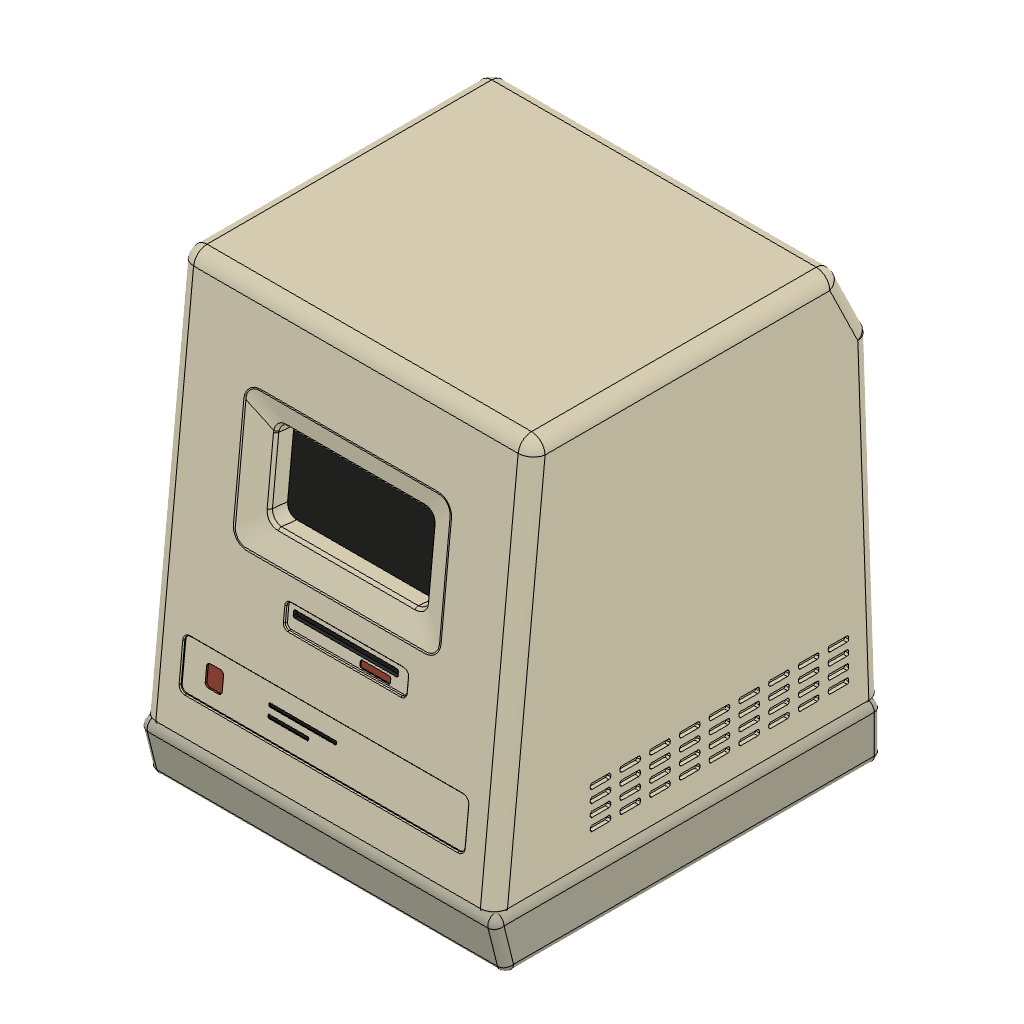
tokometer_stand_v3 (Autodesk Fusion 360 design; units mm, degrees)
part number: 2026-10-07-14-09-25-264
Autodesk Fusion 360 part; units mm, degrees
(part 1 of 2)
ref_plane "Plano de trabalho1" through (-26, 0, 0) normal (1, 0, 0) x (0, 1, 0)
sketch "Esboço1" plane through (-26, 0, 0) normal (1, 0, 0) x (0, 0, -1)
  line L0 (0, 8) -> (5.8, 65.7)
  line L1 (5.8, 65.7) -> (50.9693, 65.7)
  line L2 (50.9693, 65.7) -> (55.8466, 55.7)
  line L3 (55.8466, 55.7) -> (57.5, 8)
  line L4 (57.5, 8) -> (0, 8)
extrude "Extrusão1" add sketch "Esboço1" along normal blind 52 makes body 1
fillet "Continuous exterior corner blends" radius 2 11 edges at (-26, 36.85, -2.9) (26, 36.85, -2.9) (0, 65.7, -5.8) (-26, 65.7, -28.3846) (26, 65.7, -28.3846) (0, 65.7, -50.9693) (-26, 60.7, -53.408) (26, 60.7, -53.408) (0, 55.7, -55.8466) (-26, 31.85, -56.6733) (26, 31.85, -56.6733) on bodies 1
fillet "Lower shell edge break" radius 0.35 8 edges at (-25.4142, 8, -56.9139) (-25.4142, 8, -0.5887) (25.4142, 8, -0.5887) (25.4142, 8, -56.9139) (-26, 8, -28.7544) (0, 8, -57.5) (26, 8, -28.7544) (0, 8, 0) on bodies 1
ref_plane "Plano de trabalho2" through (-24, 0, 0) normal (1, 0, 0) x (0, 1, 0)
sketch "Esboço2" plane through (-24, 0, 0) normal (1, 0, 0) x (0, 0, -1)
  line L0 (2.5126, 8) -> (8.1116, 63.7)
  line L1 (8.1116, 63.7) -> (49.7196, 63.7)
  line L2 (49.7196, 63.7) -> (53.8638, 55.2029)
  line L3 (53.8638, 55.2029) -> (55.5, 8)
  line L4 (55.5, 8) -> (2.5126, 8)
extrude "Extrusão2" cut sketch "Esboço2" along normal blind 48 bodies 1
ref_plane "Plano de trabalho3" through (0, 35.8925, -5.3163) normal (0, 0.100016, 0.994986) x (0, -0.994986, 0.100016)
sketch "Esboço3" plane through (0, -0.17, -1.6913) normal (0, 0.100016, 0.994986) x (0, -0.994986, 0.100016)
  line L0 (-26.6423, -17.4) -> (-59.7923, -17.4)
  line L1 (-59.9923, -17.2) -> (-59.9923, 17.2)
  line L2 (-59.7923, 17.4) -> (-26.6423, 17.4)
  line L3 (-26.4423, 17.2) -> (-26.4423, -17.2)
  arc A0 (-59.9923, -17.2) -> (-59.7923, -17.4) centre (-59.7923, -17.2) ccw
  arc A1 (-59.7923, 17.4) -> (-59.9923, 17.2) centre (-59.7923, 17.2) ccw
  arc A2 (-26.4423, 17.2) -> (-26.6423, 17.4) centre (-26.6423, 17.2) ccw
  arc A3 (-26.6423, -17.4) -> (-26.4423, -17.2) centre (-26.6423, -17.2) ccw
  constraint tangent L0 A0
  constraint tangent L1 A0
  constraint tangent L1 A1
  constraint tangent L2 A1
  constraint tangent L2 A2
  constraint tangent L3 A2
  constraint tangent L3 A3
  constraint tangent L0 A3
extrude "Extrusão3" add sketch "Esboço3" against normal blind 1.5 bodies 1
sketch "Esboço4" plane through (0, 0.08, 0.7961) normal (0, 0.100016, 0.994986) x (0, -0.994986, 0.100016)
  line L0 (-36.5623, -15.22) -> (-52.1223, -15.22)
  line L1 (-54.1223, -13.22) -> (-54.1223, 13.22)
  line L2 (-52.1223, 15.22) -> (-36.5623, 15.22)
  line L3 (-34.5623, 13.22) -> (-34.5623, -13.22)
  arc A0 (-54.1223, -13.22) -> (-52.1223, -15.22) centre (-52.1223, -13.22) ccw
  arc A1 (-52.1223, 15.22) -> (-54.1223, 13.22) centre (-52.1223, 13.22) ccw
  arc A2 (-34.5623, 13.22) -> (-36.5623, 15.22) centre (-36.5623, 13.22) ccw
  arc A3 (-36.5623, -15.22) -> (-34.5623, -13.22) centre (-36.5623, -13.22) ccw
  constraint tangent L0 A0
  constraint tangent L1 A0
  constraint tangent L1 A1
  constraint tangent L2 A1
  constraint tangent L2 A2
  constraint tangent L3 A2
  constraint tangent L3 A3
  constraint tangent L0 A3
ref_plane "Plano de trabalho4" through (0, 36.0025, -4.2219) normal (0, 0.100016, 0.994986) x (0, -0.994986, 0.100016)
sketch "Esboço5" plane through (0, -0.06, -0.5969) normal (0, 0.100016, 0.994986) x (0, -0.994986, 0.100016)
  line L0 (-39.6623, -11.62) -> (-49.0223, -11.62)
  line L1 (-50.5223, -10.12) -> (-50.5223, 10.12)
  line L2 (-49.0223, 11.62) -> (-39.6623, 11.62)
  line L3 (-38.1623, 10.12) -> (-38.1623, -10.12)
  arc A0 (-50.5223, -10.12) -> (-49.0223, -11.62) centre (-49.0223, -10.12) ccw
  arc A1 (-49.0223, 11.62) -> (-50.5223, 10.12) centre (-49.0223, 10.12) ccw
  arc A2 (-38.1623, 10.12) -> (-39.6623, 11.62) centre (-39.6623, 10.12) ccw
  arc A3 (-39.6623, -11.62) -> (-38.1623, -10.12) centre (-39.6623, -10.12) ccw
  constraint tangent L0 A0
  constraint tangent L1 A0
  constraint tangent L1 A1
  constraint tangent L2 A1
  constraint tangent L2 A2
  constraint tangent L3 A2
  constraint tangent L3 A3
  constraint tangent L0 A3
loft "Recessed screen surround" cut profiles "Esboço4", "Esboço5" section 1 section 2 bodies 1
sketch "Esboço6" plane through (0, -0.06, -0.5969) normal (0, 0.100016, 0.994986) x (0, -0.994986, 0.100016)
  line L0 (-39.6623, -11.62) -> (-49.0223, -11.62)
  line L1 (-50.5223, -10.12) -> (-50.5223, 10.12)
  line L2 (-49.0223, 11.62) -> (-39.6623, 11.62)
  line L3 (-38.1623, 10.12) -> (-38.1623, -10.12)
  arc A0 (-50.5223, -10.12) -> (-49.0223, -11.62) centre (-49.0223, -10.12) ccw
  arc A1 (-49.0223, 11.62) -> (-50.5223, 10.12) centre (-49.0223, 10.12) ccw
  arc A2 (-38.1623, 10.12) -> (-39.6623, 11.62) centre (-39.6623, 10.12) ccw
  arc A3 (-39.6623, -11.62) -> (-38.1623, -10.12) centre (-39.6623, -10.12) ccw
  constraint tangent L0 A0
  constraint tangent L1 A0
  constraint tangent L1 A1
  constraint tangent L2 A1
  constraint tangent L2 A2
  constraint tangent L3 A2
  constraint tangent L3 A3
  constraint tangent L0 A3
extrude "OLED aperture" cut sketch "Esboço6" against normal blind 3.6 bodies 1
fillet "Soft screen entry lip" radius 0.7 1 edges at (15.22, 36.459, -2.8607) on bodies 1
fillet "Rounded screen throat" radius 0.5 8 edges at (-11.2027, 49.7494, -5.6037) (0, 50.209, -5.6499) (11.2027, 49.7494, -5.6037) (11.62, 44.06, -5.0318) (11.2027, 38.3706, -4.4599) (0, 37.911, -4.4137) (-11.2027, 38.3705, -4.4599) (-11.62, 44.06, -5.0318) on bodies 1
ref_plane "Plano de trabalho5" through (0, 35.7425, -6.8088) normal (0, 0.100016, 0.994986) x (0, -0.994986, 0.100016)
ref_plane "Plano de trabalho6" through (0, 35.4524, -9.6943) normal (0, 0.100016, 0.994986) x (0, -0.994986, 0.100016)
ref_plane "Plano de trabalho7" through (0, 35.4824, -9.3958) normal (0, 0.100016, 0.994986) x (0, -0.994986, 0.100016)
sketch "Esboço7" plane through (0, -0.32, -3.1838) normal (0, 0.100016, 0.994986) x (0, -0.994986, 0.100016)
  line L0 (-28.6423, -15.4) -> (-57.7923, -15.4)
  line L1 (-57.9923, -15.2) -> (-57.9923, -14.1)
  line L2 (-57.7923, -13.9) -> (-28.6423, -13.9)
  line L3 (-28.4423, -14.1) -> (-28.4423, -15.2)
  arc A0 (-57.9923, -15.2) -> (-57.7923, -15.4) centre (-57.7923, -15.2) ccw
  arc A1 (-57.7923, -13.9) -> (-57.9923, -14.1) centre (-57.7923, -14.1) ccw
  arc A2 (-28.4423, -14.1) -> (-28.6423, -13.9) centre (-28.6423, -14.1) ccw
  arc A3 (-28.6423, -15.4) -> (-28.4423, -15.2) centre (-28.6423, -15.2) ccw
  constraint tangent L0 A0
  constraint tangent L1 A0
  constraint tangent L1 A1
  constraint tangent L2 A1
  constraint tangent L2 A2
  constraint tangent L3 A2
  constraint tangent L3 A3
  constraint tangent L0 A3
extrude "Extrusão5" add sketch "Esboço7" against normal blind 2.9 bodies 1
sketch "Esboço8" plane through (0, -0.6101, -6.0693) normal (0, 0.100016, 0.994986) x (0, -0.994986, 0.100016)
  line L0 (-28.6423, -15.4) -> (-57.7923, -15.4)
  line L1 (-57.9923, -15.2) -> (-57.9923, -12.65)
  line L2 (-57.7923, -12.45) -> (-28.6423, -12.45)
  line L3 (-28.4423, -12.65) -> (-28.4423, -15.2)
  arc A0 (-57.9923, -15.2) -> (-57.7923, -15.4) centre (-57.7923, -15.2) ccw
  arc A1 (-57.7923, -12.45) -> (-57.9923, -12.65) centre (-57.7923, -12.65) ccw
  arc A2 (-28.4423, -12.65) -> (-28.6423, -12.45) centre (-28.6423, -12.65) ccw
  arc A3 (-28.6423, -15.4) -> (-28.4423, -15.2) centre (-28.6423, -15.2) ccw
  constraint tangent L0 A0
  constraint tangent L1 A0
  constraint tangent L1 A1
  constraint tangent L2 A1
  constraint tangent L2 A2
  constraint tangent L3 A2
  constraint tangent L3 A3
  constraint tangent L0 A3
extrude "Extrusão6" add sketch "Esboço8" against normal blind 1.2 bodies 1
sketch "Esboço9" plane through (0, -0.32, -3.1838) normal (0, 0.100016, 0.994986) x (0, -0.994986, 0.100016)
  line L0 (-56.6923, -14.15) -> (-57.7923, -14.15)
  line L1 (-57.9923, -13.95) -> (-57.9923, -11.35)
  line L2 (-57.7923, -11.15) -> (-56.6923, -11.15)
  line L3 (-56.4923, -11.35) -> (-56.4923, -13.95)
  arc A0 (-57.9923, -13.95) -> (-57.7923, -14.15) centre (-57.7923, -13.95) ccw
  arc A1 (-57.7923, -11.15) -> (-57.9923, -11.35) centre (-57.7923, -11.35) ccw
  arc A2 (-56.4923, -11.35) -> (-56.6923, -11.15) centre (-56.6923, -11.35) ccw
  arc A3 (-56.6923, -14.15) -> (-56.4923, -13.95) centre (-56.6923, -13.95) ccw
  constraint tangent L0 A0
  constraint tangent L1 A0
  constraint tangent L1 A1
  constraint tangent L2 A1
  constraint tangent L2 A2
  constraint tangent L3 A2
  constraint tangent L3 A3
  constraint tangent L0 A3
extrude "Extrusão7" add sketch "Esboço9" against normal blind 2.9 bodies 1
sketch "Esboço10" plane through (0, -0.5801, -5.7708) normal (0, 0.100016, 0.994986) x (0, -0.994986, 0.100016)
  line L0 (-34.0923, -13.53) -> (-36.6923, -13.53)
  line L1 (-36.8923, -13.33) -> (-36.8923, -12.77)
  line L2 (-36.6923, -12.57) -> (-34.0923, -12.57)
  line L3 (-33.8923, -12.77) -> (-33.8923, -13.33)
  arc A0 (-36.8923, -13.33) -> (-36.6923, -13.53) centre (-36.6923, -13.33) ccw
  arc A1 (-36.6923, -12.57) -> (-36.8923, -12.77) centre (-36.6923, -12.77) ccw
  arc A2 (-33.8923, -12.77) -> (-34.0923, -12.57) centre (-34.0923, -12.77) ccw
  arc A3 (-34.0923, -13.53) -> (-33.8923, -13.33) centre (-34.0923, -13.33) ccw
  constraint tangent L0 A0
  constraint tangent L1 A0
  constraint tangent L1 A1
  constraint tangent L2 A1
  constraint tangent L2 A2
  constraint tangent L3 A2
  constraint tangent L3 A3
  constraint tangent L0 A3
extrude "Extrusão8" add sketch "Esboço10" against normal blind 0.3 bodies 1
sketch "Esboço11" plane through (0, -0.5801, -5.7708) normal (0, 0.100016, 0.994986) x (0, -0.994986, 0.100016)
  line L0 (-47.9923, -13.53) -> (-50.5923, -13.53)
  line L1 (-50.7923, -13.33) -> (-50.7923, -12.77)
  line L2 (-50.5923, -12.57) -> (-47.9923, -12.57)
  line L3 (-47.7923, -12.77) -> (-47.7923, -13.33)
  arc A0 (-50.7923, -13.33) -> (-50.5923, -13.53) centre (-50.5923, -13.33) ccw
  arc A1 (-50.5923, -12.57) -> (-50.7923, -12.77) centre (-50.5923, -12.77) ccw
  arc A2 (-47.7923, -12.77) -> (-47.9923, -12.57) centre (-47.9923, -12.77) ccw
  arc A3 (-47.9923, -13.53) -> (-47.7923, -13.33) centre (-47.9923, -13.33) ccw
  constraint tangent L0 A0
  constraint tangent L1 A0
  constraint tangent L1 A1
  constraint tangent L2 A1
  constraint tangent L2 A2
  constraint tangent L3 A2
  constraint tangent L3 A3
  constraint tangent L0 A3
extrude "Extrusão9" add sketch "Esboço11" against normal blind 0.3 bodies 1
sketch "Esboço12" plane through (0, -0.32, -3.1838) normal (0, 0.100016, 0.994986) x (0, -0.994986, 0.100016)
  line L0 (-28.6423, 13.9) -> (-57.7923, 13.9)
  line L1 (-57.9923, 14.1) -> (-57.9923, 15.2)
  line L2 (-57.7923, 15.4) -> (-28.6423, 15.4)
  line L3 (-28.4423, 15.2) -> (-28.4423, 14.1)
  arc A0 (-57.9923, 14.1) -> (-57.7923, 13.9) centre (-57.7923, 14.1) ccw
  arc A1 (-57.7923, 15.4) -> (-57.9923, 15.2) centre (-57.7923, 15.2) ccw
  arc A2 (-28.4423, 15.2) -> (-28.6423, 15.4) centre (-28.6423, 15.2) ccw
  arc A3 (-28.6423, 13.9) -> (-28.4423, 14.1) centre (-28.6423, 14.1) ccw
  constraint tangent L0 A0
  constraint tangent L1 A0
  constraint tangent L1 A1
  constraint tangent L2 A1
  constraint tangent L2 A2
  constraint tangent L3 A2
  constraint tangent L3 A3
  constraint tangent L0 A3
extrude "Extrusão10" add sketch "Esboço12" against normal blind 2.9 bodies 1
sketch "Esboço13" plane through (0, -0.6101, -6.0693) normal (0, 0.100016, 0.994986) x (0, -0.994986, 0.100016)
  line L0 (-28.6423, 12.45) -> (-57.7923, 12.45)
  line L1 (-57.9923, 12.65) -> (-57.9923, 15.2)
  line L2 (-57.7923, 15.4) -> (-28.6423, 15.4)
  line L3 (-28.4423, 15.2) -> (-28.4423, 12.65)
  arc A0 (-57.9923, 12.65) -> (-57.7923, 12.45) centre (-57.7923, 12.65) ccw
  arc A1 (-57.7923, 15.4) -> (-57.9923, 15.2) centre (-57.7923, 15.2) ccw
  arc A2 (-28.4423, 15.2) -> (-28.6423, 15.4) centre (-28.6423, 15.2) ccw
  arc A3 (-28.6423, 12.45) -> (-28.4423, 12.65) centre (-28.6423, 12.65) ccw
  constraint tangent L0 A0
  constraint tangent L1 A0
  constraint tangent L1 A1
  constraint tangent L2 A1
  constraint tangent L2 A2
  constraint tangent L3 A2
  constraint tangent L3 A3
  constraint tangent L0 A3
extrude "Extrusão11" add sketch "Esboço13" against normal blind 1.2 bodies 1
sketch "Esboço14" plane through (0, -0.32, -3.1838) normal (0, 0.100016, 0.994986) x (0, -0.994986, 0.100016)
  line L0 (-56.6923, 11.15) -> (-57.7923, 11.15)
  line L1 (-57.9923, 11.35) -> (-57.9923, 13.95)
  line L2 (-57.7923, 14.15) -> (-56.6923, 14.15)
  line L3 (-56.4923, 13.95) -> (-56.4923, 11.35)
  arc A0 (-57.9923, 11.35) -> (-57.7923, 11.15) centre (-57.7923, 11.35) ccw
  arc A1 (-57.7923, 14.15) -> (-57.9923, 13.95) centre (-57.7923, 13.95) ccw
  arc A2 (-56.4923, 13.95) -> (-56.6923, 14.15) centre (-56.6923, 13.95) ccw
  arc A3 (-56.6923, 11.15) -> (-56.4923, 11.35) centre (-56.6923, 11.35) ccw
  constraint tangent L0 A0
  constraint tangent L1 A0
  constraint tangent L1 A1
  constraint tangent L2 A1
  constraint tangent L2 A2
  constraint tangent L3 A2
  constraint tangent L3 A3
  constraint tangent L0 A3
extrude "Extrusão12" add sketch "Esboço14" against normal blind 2.9 bodies 1
sketch "Esboço15" plane through (0, -0.5801, -5.7708) normal (0, 0.100016, 0.994986) x (0, -0.994986, 0.100016)
  line L0 (-34.0923, 12.57) -> (-36.6923, 12.57)
  line L1 (-36.8923, 12.77) -> (-36.8923, 13.33)
  line L2 (-36.6923, 13.53) -> (-34.0923, 13.53)
  line L3 (-33.8923, 13.33) -> (-33.8923, 12.77)
  arc A0 (-36.8923, 12.77) -> (-36.6923, 12.57) centre (-36.6923, 12.77) ccw
  arc A1 (-36.6923, 13.53) -> (-36.8923, 13.33) centre (-36.6923, 13.33) ccw
  arc A2 (-33.8923, 13.33) -> (-34.0923, 13.53) centre (-34.0923, 13.33) ccw
  arc A3 (-34.0923, 12.57) -> (-33.8923, 12.77) centre (-34.0923, 12.77) ccw
  constraint tangent L0 A0
  constraint tangent L1 A0
  constraint tangent L1 A1
  constraint tangent L2 A1
  constraint tangent L2 A2
  constraint tangent L3 A2
  constraint tangent L3 A3
  constraint tangent L0 A3
extrude "Extrusão13" add sketch "Esboço15" against normal blind 0.3 bodies 1
sketch "Esboço16" plane through (0, -0.5801, -5.7708) normal (0, 0.100016, 0.994986) x (0, -0.994986, 0.100016)
  line L0 (-47.9923, 12.57) -> (-50.5923, 12.57)
  line L1 (-50.7923, 12.77) -> (-50.7923, 13.33)
  line L2 (-50.5923, 13.53) -> (-47.9923, 13.53)
  line L3 (-47.7923, 13.33) -> (-47.7923, 12.77)
  arc A0 (-50.7923, 12.77) -> (-50.5923, 12.57) centre (-50.5923, 12.77) ccw
  arc A1 (-50.5923, 13.53) -> (-50.7923, 13.33) centre (-50.5923, 13.33) ccw
  arc A2 (-47.7923, 13.33) -> (-47.9923, 13.53) centre (-47.9923, 13.33) ccw
  arc A3 (-47.9923, 12.57) -> (-47.7923, 12.77) centre (-47.9923, 12.77) ccw
  constraint tangent L0 A0
  constraint tangent L1 A0
  constraint tangent L1 A1
  constraint tangent L2 A1
  constraint tangent L2 A2
  constraint tangent L3 A2
  constraint tangent L3 A3
  constraint tangent L0 A3
extrude "Extrusão14" add sketch "Esboço16" against normal blind 0.3 bodies 1
ref_plane "Plano de trabalho8" through (0, 0, -58.5) normal (0, 0, 1) x (1, 0, 0)
sketch "Esboço17" plane through (0, 0, -58.5) normal (0, 0, 1) x (1, 0, 0)
  line L0 (-5, 10.2) -> (5, 10.2)
  line L1 (6.5, 11.7) -> (6.5, 15.7)
  line L2 (5, 17.2) -> (-5, 17.2)
  line L3 (-6.5, 15.7) -> (-6.5, 11.7)
  arc A0 (5, 10.2) -> (6.5, 11.7) centre (5, 11.7) ccw
  arc A1 (6.5, 15.7) -> (5, 17.2) centre (5, 15.7) ccw
  arc A2 (-5, 17.2) -> (-6.5, 15.7) centre (-5, 15.7) ccw
  arc A3 (-6.5, 11.7) -> (-5, 10.2) centre (-5, 11.7) ccw
  constraint tangent L0 A0
  constraint tangent L1 A0
  constraint tangent L1 A1
  constraint tangent L2 A1
  constraint tangent L2 A2
  constraint tangent L3 A2
  constraint tangent L3 A3
  constraint tangent L0 A3
extrude "Extrusão15" cut sketch "Esboço17" along normal blind 6 bodies 1
ref_plane "Plano de trabalho9" through (0, 8.65, 0) normal (0, 1, 0) x (0, 0, 1)
sketch "Esboço18" plane through (0, 8.65, 0) normal (0, 1, 0) x (1, 0, 0)
  line L0 (23.5, 18.0063) -> (24.5, 18.0063)
  line L1 (24.5, 18.0063) -> (24.5, 40.0063)
  line L2 (24.5, 40.0063) -> (23.5, 40.0063)
  line L3 (23.5, 40.0063) -> (23.5, 18.0063)
extrude "Extrusão16" cut sketch "Esboço18" along normal blind 1 bodies 1
ref_plane "Plano de trabalho10" through (0, 8.65, 0) normal (0, 1, 0) x (0, 0, 1)
sketch "Esboço19" plane through (0, 8.65, 0) normal (0, 1, 0) x (1, 0, 0)
  line L0 (-24.5, 18.0063) -> (-23.5, 18.0063)
  line L1 (-23.5, 18.0063) -> (-23.5, 40.0063)
  line L2 (-23.5, 40.0063) -> (-24.5, 40.0063)
  line L3 (-24.5, 40.0063) -> (-24.5, 18.0063)
extrude "Extrusão17" cut sketch "Esboço19" along normal blind 1 bodies 1
ref_plane "Plano de trabalho11" through (-26.4, 0, 0) normal (1, 0, 0) x (0, 1, 0)
sketch "Esboço20" plane through (-26.4, 0, 0) normal (1, 0, 0) x (0, 0, -1)
  line L0 (1.6, 0) -> (57.1, 0)
  line L1 (57.1, 0) -> (57.1, 8)
  line L2 (57.1, 8) -> (-0.4, 8)
  line L3 (-0.4, 8) -> (1.6, 0)
extrude "Extrusão18" add sketch "Esboço20" along normal blind 52.8 separate body makes body 2
fillet "Molded base perimeter" radius 1.2 12 edges at (-26.4, 8, -28.35) (0, 8, 0.4) (26.4, 8, -28.35) (0, 8, -57.1) (-26.4, 4, -57.1) (26.4, 4, -57.1) (0, 0, -57.1) (-26.4, 0, -29.35) (26.4, 0, -29.35) (0, 0, -1.6) (-26.4, 4, -0.6) (26.4, 4, -0.6) on bodies 2
ref_plane "Plano de trabalho12" through (0, 8, 0) normal (0, 1, 0) x (0, 0, 1)
sketch "Esboço21" plane through (0, 8, 0) normal (0, 1, 0) x (1, 0, 0)
  line L0 (-23.8, 2.9438) -> (23.8, 2.9438)
  line L1 (23.8, 2.9438) -> (23.8, 55.3)
  line L2 (23.8, 55.3) -> (-23.8, 55.3)
  line L3 (-23.8, 55.3) -> (-23.8, 2.9438)
  line L4 (-22.2, 4.5438) -> (22.2, 4.5438)
  line L5 (22.2, 4.5438) -> (22.2, 53.7)
  line L6 (22.2, 53.7) -> (-22.2, 53.7)
  line L7 (-22.2, 53.7) -> (-22.2, 4.5438)
extrude "Extrusão19" add sketch "Esboço21" along normal blind 2.3 bodies 2
ref_plane "Plano de trabalho13" through (0, 8, 0) normal (0, 1, 0) x (0, 0, 1)
sketch "Esboço22" plane through (0, 8, 0) normal (0, 1, 0) x (1, 0, 0)
  line L0 (-7.5, 53.2) -> (7.5, 53.2)
  line L1 (7.5, 53.2) -> (7.5, 55.8)
  line L2 (7.5, 55.8) -> (-7.5, 55.8)
  line L3 (-7.5, 55.8) -> (-7.5, 53.2)
extrude "Extrusão20" cut sketch "Esboço22" along normal blind 2.8 bodies 2
ref_plane "Plano de trabalho14" through (0, 8.75, 0) normal (0, 1, 0) x (0, 0, 1)
sketch "Esboço23" plane through (0, 8.75, 0) normal (0, 1, 0) x (1, 0, 0)
  line L0 (23.6, 19.0063) -> (24.2, 19.0063)
  line L1 (24.2, 19.0063) -> (24.2, 39.0063)
  line L2 (24.2, 39.0063) -> (23.6, 39.0063)
  line L3 (23.6, 39.0063) -> (23.6, 19.0063)
extrude "Extrusão21" add sketch "Esboço23" along normal blind 0.8 bodies 2
ref_plane "Plano de trabalho15" through (0, 8.75, 0) normal (0, 1, 0) x (0, 0, 1)
sketch "Esboço24" plane through (0, 8.75, 0) normal (0, 1, 0) x (1, 0, 0)
  line L0 (-24.2, 19.0063) -> (-23.6, 19.0063)
  line L1 (-23.6, 19.0063) -> (-23.6, 39.0063)
  line L2 (-23.6, 39.0063) -> (-24.2, 39.0063)
  line L3 (-24.2, 39.0063) -> (-24.2, 19.0063)
extrude "Extrusão22" add sketch "Esboço24" along normal blind 0.8 bodies 2
ref_plane "Plano de trabalho16" through (0, 1.5, 0) normal (0, 1, 0) x (0, 0, 1)
sketch "Esboço25" plane through (0, 1.5, 0) normal (0, 1, 0) x (1, 0, 0)
  line L0 (-13.35, 5.8811) -> (-12.05, 5.8811)
  line L1 (-12.05, 5.8811) -> (-12.05, 52.3811)
  line L2 (-12.05, 52.3811) -> (-13.35, 52.3811)
  line L3 (-13.35, 52.3811) -> (-13.35, 5.8811)
extrude "Extrusão23" cut sketch "Esboço25" along normal blind 7 bodies 2
ref_plane "Plano de trabalho17" through (0, 1.5, 0) normal (0, 1, 0) x (0, 0, 1)
sketch "Esboço26" plane through (0, 1.5, 0) normal (0, 1, 0) x (1, 0, 0)
  line L0 (12.05, 5.8811) -> (13.35, 5.8811)
  line L1 (13.35, 5.8811) -> (13.35, 52.3811)
  line L2 (13.35, 52.3811) -> (12.05, 52.3811)
  line L3 (12.05, 52.3811) -> (12.05, 5.8811)
extrude "Extrusão24" cut sketch "Esboço26" along normal blind 7 bodies 2
ref_plane "Plano de trabalho18" through (0, 0, -6.8) normal (0, 0, 1) x (1, 0, 0)
sketch "Esboço27" plane through (0, 0, -6.8) normal (0, 0, 1) x (1, 0, 0)
  line L0 (-13.65, 28.3) -> (13.65, 28.3)
  line L1 (13.65, 28.3) -> (13.65, 56.1)
  line L2 (13.65, 56.1) -> (-13.65, 56.1)
  line L3 (-13.65, 56.1) -> (-13.65, 28.3)
extrude "Extrusão25" add sketch "Esboço27" along normal blind 1.6 separate body makes body 3
ref_plane "Plano de trabalho19" through (0, 0, -5.2) normal (0, 0, 1) x (1, 0, 0)
sketch "Esboço28" plane through (0, 0, -5.2) normal (0, 0, 1) x (1, 0, 0)
  line L0 (-13.35, 32.55) -> (13.35, 32.55)
  line L1 (13.35, 32.55) -> (13.35, 51.85)
  line L2 (13.35, 51.85) -> (-13.35, 51.85)
  line L3 (-13.35, 51.85) -> (-13.35, 32.55)
extrude "Extrusão26" add sketch "Esboço28" along normal blind 1.2 bodies 3
move_body "Mover1" bodies 3 to x (1, 0, 0) y (0, 0.994986, -0.100016) z (0, 0.100016, 0.994986) at (0, 0.2216, 0.7819)
ref_plane "Plano de trabalho20" through (0, 10.5, 0) normal (0, 1, 0) x (0, 0, 1)
sketch "Esboço29" plane through (0, 10.5, 0) normal (0, 1, 0) x (1, 0, 0)
  line L0 (-14.25, 3.3811) -> (14.25, 3.3811)
  line L1 (14.25, 3.3811) -> (14.25, 54.8811)
  line L2 (14.25, 54.8811) -> (-14.25, 54.8811)
  line L3 (-14.25, 54.8811) -> (-14.25, 3.3811)
extrude "Extrusão27" add sketch "Esboço29" along normal blind 1.6 separate body makes body 4
ref_plane "Plano de trabalho21" through (0, 8, 0) normal (0, 1, 0) x (0, 0, 1)
sketch "Esboço30" plane through (0, 8, 0) normal (0, 1, 0) x (1, 0, 0)
  line L0 (-13.97, 10.1311) -> (-11.43, 10.1311)
  line L1 (-11.43, 10.1311) -> (-11.43, 48.1311)
  line L2 (-11.43, 48.1311) -> (-13.97, 48.1311)
  line L3 (-13.97, 48.1311) -> (-13.97, 10.1311)
extrude "Extrusão28" add sketch "Esboço30" along normal blind 2.5 bodies 4
ref_plane "Plano de trabalho22" through (0, 8, 0) normal (0, 1, 0) x (0, 0, 1)
sketch "Esboço31" plane through (0, 8, 0) normal (0, 1, 0) x (1, 0, 0)
  line L0 (11.43, 10.1311) -> (13.97, 10.1311)
  line L1 (13.97, 10.1311) -> (13.97, 48.1311)
  line L2 (13.97, 48.1311) -> (11.43, 48.1311)
  line L3 (11.43, 48.1311) -> (11.43, 10.1311)
extrude "Extrusão29" add sketch "Esboço31" along normal blind 2.5 bodies 4
ref_plane "Plano de trabalho23" through (0, 12.1, 0) normal (0, 1, 0) x (0, 0, 1)
sketch "Esboço32" plane through (0, 12.1, 0) normal (0, 1, 0) x (1, 0, 0)
  line L0 (-9, 3.8811) -> (9, 3.8811)
  line L1 (9, 3.8811) -> (9, 21.8811)
  line L2 (9, 21.8811) -> (-9, 21.8811)
  line L3 (-9, 21.8811) -> (-9, 3.8811)
extrude "Extrusão30" add sketch "Esboço32" along normal blind 3.1 bodies 4
ref_plane "Plano de trabalho24" through (0, 12.1, 0) normal (0, 1, 0) x (0, 0, 1)
sketch "Esboço33" plane through (0, 12.1, 0) normal (0, 1, 0) x (1, 0, 0)
  line L0 (-4.5, 47.5811) -> (4.5, 47.5811)
  line L1 (4.5, 47.5811) -> (4.5, 54.8811)
  line L2 (4.5, 54.8811) -> (-4.5, 54.8811)
  line L3 (-4.5, 54.8811) -> (-4.5, 47.5811)
extrude "Extrusão31" add sketch "Esboço33" along normal blind 3.2 bodies 4
sketch "Esboço34" plane through (0, 0.08, 0.7961) normal (0, 0.100016, 0.994986) x (0, -0.994986, 0.100016)
  line L0 (-28.5123, -7) -> (-30.6123, -7)
  line L1 (-31.2623, -6.35) -> (-31.2623, 10.35)
  line L2 (-30.6123, 11) -> (-28.5123, 11)
  line L3 (-27.8623, 10.35) -> (-27.8623, -6.35)
  arc A0 (-31.2623, -6.35) -> (-30.6123, -7) centre (-30.6123, -6.35) ccw
  arc A1 (-30.6123, 11) -> (-31.2623, 10.35) centre (-30.6123, 10.35) ccw
  arc A2 (-27.8623, 10.35) -> (-28.5123, 11) centre (-28.5123, 10.35) ccw
  arc A3 (-28.5123, -7) -> (-27.8623, -6.35) centre (-28.5123, -6.35) ccw
  constraint tangent L0 A0
  constraint tangent L1 A0
  constraint tangent L1 A1
  constraint tangent L2 A1
  constraint tangent L2 A2
  constraint tangent L3 A2
  constraint tangent L3 A3
  constraint tangent L0 A3
extrude "Drive bezel" cut sketch "Esboço34" against normal blind 0.45 bodies 1
sketch "Esboço35" plane through (0, 0.08, 0.7961) normal (0, 0.100016, 0.994986) x (0, -0.994986, 0.100016)
  line L0 (-29.6641, -6.25) -> (-30.1641, -6.25)
  line L1 (-30.4141, -6) -> (-30.4141, 9)
  line L2 (-30.1641, 9.25) -> (-29.6641, 9.25)
  line L3 (-29.4141, 9) -> (-29.4141, -6)
  arc A0 (-30.4141, -6) -> (-30.1641, -6.25) centre (-30.1641, -6) ccw
  arc A1 (-30.1641, 9.25) -> (-30.4141, 9) centre (-30.1641, 9) ccw
  arc A2 (-29.4141, 9) -> (-29.6641, 9.25) centre (-29.6641, 9) ccw
  arc A3 (-29.6641, -6.25) -> (-29.4141, -6) centre (-29.6641, -6) ccw
  constraint tangent L0 A0
  constraint tangent L1 A0
  constraint tangent L1 A1
  constraint tangent L2 A1
  constraint tangent L2 A2
  constraint tangent L3 A2
  constraint tangent L3 A3
  constraint tangent L0 A3
extrude "Drive slot" cut sketch "Esboço35" against normal blind 1 bodies 1
sketch "Esboço36" plane through (0, 0.08, 0.7961) normal (0, 0.100016, 0.994986) x (0, -0.994986, 0.100016)
  line L0 (-28.3073, 3.75) -> (-28.8073, 3.75)
  line L1 (-29.0573, 4) -> (-29.0573, 8)
  line L2 (-28.8073, 8.25) -> (-28.3073, 8.25)
  line L3 (-28.0573, 8) -> (-28.0573, 4)
  arc A0 (-29.0573, 4) -> (-28.8073, 3.75) centre (-28.8073, 4) ccw
  arc A1 (-28.8073, 8.25) -> (-29.0573, 8) centre (-28.8073, 8) ccw
  arc A2 (-28.0573, 8) -> (-28.3073, 8.25) centre (-28.3073, 8) ccw
  arc A3 (-28.3073, 3.75) -> (-28.0573, 4) centre (-28.3073, 4) ccw
  constraint tangent L0 A0
  constraint tangent L1 A0
  constraint tangent L1 A1
  constraint tangent L2 A1
  constraint tangent L2 A2
  constraint tangent L3 A2
  constraint tangent L3 A3
  constraint tangent L0 A3
extrude "Eject accent" cut sketch "Esboço36" against normal blind 0.6 bodies 1
sketch "Esboço37" plane through (0, 0.08, 0.7961) normal (0, 0.100016, 0.994986) x (0, -0.994986, 0.100016)
  line L0 (-14.3052, -21) -> (-19.7052, -21)
  line L1 (-20.5052, -20.2) -> (-20.5052, 20.2)
  line L2 (-19.7052, 21) -> (-14.3052, 21)
  line L3 (-13.5052, 20.2) -> (-13.5052, -20.2)
  arc A0 (-20.5052, -20.2) -> (-19.7052, -21) centre (-19.7052, -20.2) ccw
  arc A1 (-19.7052, 21) -> (-20.5052, 20.2) centre (-19.7052, 20.2) ccw
  arc A2 (-13.5052, 20.2) -> (-14.3052, 21) centre (-14.3052, 20.2) ccw
  arc A3 (-14.3052, -21) -> (-13.5052, -20.2) centre (-14.3052, -20.2) ccw
  constraint tangent L0 A0
  constraint tangent L1 A0
  constraint tangent L1 A1
  constraint tangent L2 A1
  constraint tangent L2 A2
  constraint tangent L3 A2
  constraint tangent L3 A3
  constraint tangent L0 A3
extrude "Lower fascia inset" cut sketch "Esboço37" against normal blind 0.3 bodies 1
sketch "Esboço38" plane through (0, 0.08, 0.7961) normal (0, 0.100016, 0.994986) x (0, -0.994986, 0.100016)
  line L0 (-16.0052, -17.75) -> (-18.0052, -17.75)
  line L1 (-18.5052, -17.25) -> (-18.5052, -15.75)
  line L2 (-18.0052, -15.25) -> (-16.0052, -15.25)
  line L3 (-15.5052, -15.75) -> (-15.5052, -17.25)
  arc A0 (-18.5052, -17.25) -> (-18.0052, -17.75) centre (-18.0052, -17.25) ccw
  arc A1 (-18.0052, -15.25) -> (-18.5052, -15.75) centre (-18.0052, -15.75) ccw
  arc A2 (-15.5052, -15.75) -> (-16.0052, -15.25) centre (-16.0052, -15.75) ccw
  arc A3 (-16.0052, -17.75) -> (-15.5052, -17.25) centre (-16.0052, -17.25) ccw
  constraint tangent L0 A0
  constraint tangent L1 A0
  constraint tangent L1 A1
  constraint tangent L2 A1
  constraint tangent L2 A2
  constraint tangent L3 A2
  constraint tangent L3 A3
  constraint tangent L0 A3
extrude "Lower fascia badge" cut sketch "Esboço38" against normal blind 0.55 bodies 1
sketch "Esboço39" plane through (0, 0.08, 0.7961) normal (0, 0.100016, 0.994986) x (0, -0.994986, 0.100016)
  line L0 (-17.6088, -8.5) -> (-17.8088, -8.5)
  line L1 (-17.9588, -8.35) -> (-17.9588, 1.35)
  line L2 (-17.8088, 1.5) -> (-17.6088, 1.5)
  line L3 (-17.4588, 1.35) -> (-17.4588, -8.35)
  arc A0 (-17.9588, -8.35) -> (-17.8088, -8.5) centre (-17.8088, -8.35) ccw
  arc A1 (-17.8088, 1.5) -> (-17.9588, 1.35) centre (-17.8088, 1.35) ccw
  arc A2 (-17.4588, 1.35) -> (-17.6088, 1.5) centre (-17.6088, 1.35) ccw
  arc A3 (-17.6088, -8.5) -> (-17.4588, -8.35) centre (-17.6088, -8.35) ccw
  constraint tangent L0 A0
  constraint tangent L1 A0
  constraint tangent L1 A1
  constraint tangent L2 A1
  constraint tangent L2 A2
  constraint tangent L3 A2
  constraint tangent L3 A3
  constraint tangent L0 A3
extrude "Label line 1" cut sketch "Esboço39" against normal blind 0.45 bodies 1
sketch "Esboço40" plane through (0, 0.08, 0.7961) normal (0, 0.100016, 0.994986) x (0, -0.994986, 0.100016)
  line L0 (-16.2017, -8.5) -> (-16.4017, -8.5)
  line L1 (-16.5517, -8.35) -> (-16.5517, -2.65)
  line L2 (-16.4017, -2.5) -> (-16.2017, -2.5)
  line L3 (-16.0517, -2.65) -> (-16.0517, -8.35)
  arc A0 (-16.5517, -8.35) -> (-16.4017, -8.5) centre (-16.4017, -8.35) ccw
  arc A1 (-16.4017, -2.5) -> (-16.5517, -2.65) centre (-16.4017, -2.65) ccw
  arc A2 (-16.0517, -2.65) -> (-16.2017, -2.5) centre (-16.2017, -2.65) ccw
  arc A3 (-16.2017, -8.5) -> (-16.0517, -8.35) centre (-16.2017, -8.35) ccw
  constraint tangent L0 A0
  constraint tangent L1 A0
  constraint tangent L1 A1
  constraint tangent L2 A1
  constraint tangent L2 A2
  constraint tangent L3 A2
  constraint tangent L3 A3
  constraint tangent L0 A3
extrude "Label line 2" cut sketch "Esboço40" against normal blind 0.45 bodies 1
fillet "Drive bezel edge" radius 0.15 8 edges at (-7, 29.4941, -2.1606) (-6.8096, 27.9921, -2.0096) (2, 27.8026, -1.9906) (10.8096, 27.9921, -2.0096) (11, 29.4941, -2.1606) (10.8096, 30.9962, -2.3116) (2, 31.1856, -2.3306) (-6.8096, 30.9962, -2.3116) on bodies 1
fillet "Lower fascia edge" radius 0.15 8 edges at (-21, 17, -0.9047) (-20.7657, 20.2493, -1.2313) (0, 20.4825, -1.2547) (20.7657, 20.2493, -1.2313) (21, 17, -0.9047) (20.7657, 13.7507, -0.5781) (0, 13.5175, -0.5546) (-20.7657, 13.7507, -0.5781) on bodies 1
ref_plane "Plano de trabalho25" through (25.45, 0, 0) normal (1, 0, 0) x (0, 1, 0)
sketch "Esboço41" plane through (25.45, 0, 0) normal (1, 0, 0) x (0, 0, -1)
  line L0 (49.75, 12) -> (52.25, 12)
  line L1 (52.5, 12.25) -> (52.5, 12.55)
  line L2 (52.25, 12.8) -> (49.75, 12.8)
  line L3 (49.5, 12.55) -> (49.5, 12.25)
  arc A0 (52.25, 12) -> (52.5, 12.25) centre (52.25, 12.25) ccw
  arc A1 (52.5, 12.55) -> (52.25, 12.8) centre (52.25, 12.55) ccw
  arc A2 (49.75, 12.8) -> (49.5, 12.55) centre (49.75, 12.55) ccw
  arc A3 (49.5, 12.25) -> (49.75, 12) centre (49.75, 12.25) ccw
  line L4 (45.35, 12) -> (47.85, 12)
  line L5 (48.1, 12.25) -> (48.1, 12.55)
  line L6 (47.85, 12.8) -> (45.35, 12.8)
  line L7 (45.1, 12.55) -> (45.1, 12.25)
  arc A4 (47.85, 12) -> (48.1, 12.25) centre (47.85, 12.25) ccw
  arc A5 (48.1, 12.55) -> (47.85, 12.8) centre (47.85, 12.55) ccw
  arc A6 (45.35, 12.8) -> (45.1, 12.55) centre (45.35, 12.55) ccw
  arc A7 (45.1, 12.25) -> (45.35, 12) centre (45.35, 12.25) ccw
  line L8 (40.95, 12) -> (43.45, 12)
  line L9 (43.7, 12.25) -> (43.7, 12.55)
  line L10 (43.45, 12.8) -> (40.95, 12.8)
  line L11 (40.7, 12.55) -> (40.7, 12.25)
  arc A8 (43.45, 12) -> (43.7, 12.25) centre (43.45, 12.25) ccw
  arc A9 (43.7, 12.55) -> (43.45, 12.8) centre (43.45, 12.55) ccw
  arc A10 (40.95, 12.8) -> (40.7, 12.55) centre (40.95, 12.55) ccw
  arc A11 (40.7, 12.25) -> (40.95, 12) centre (40.95, 12.25) ccw
  line L12 (36.55, 12) -> (39.05, 12)
  line L13 (39.3, 12.25) -> (39.3, 12.55)
  line L14 (39.05, 12.8) -> (36.55, 12.8)
  line L15 (36.3, 12.55) -> (36.3, 12.25)
  arc A12 (39.05, 12) -> (39.3, 12.25) centre (39.05, 12.25) ccw
  arc A13 (39.3, 12.55) -> (39.05, 12.8) centre (39.05, 12.55) ccw
  arc A14 (36.55, 12.8) -> (36.3, 12.55) centre (36.55, 12.55) ccw
  arc A15 (36.3, 12.25) -> (36.55, 12) centre (36.55, 12.25) ccw
  line L16 (32.15, 12) -> (34.65, 12)
  line L17 (34.9, 12.25) -> (34.9, 12.55)
  line L18 (34.65, 12.8) -> (32.15, 12.8)
  line L19 (31.9, 12.55) -> (31.9, 12.25)
  arc A16 (34.65, 12) -> (34.9, 12.25) centre (34.65, 12.25) ccw
  arc A17 (34.9, 12.55) -> (34.65, 12.8) centre (34.65, 12.55) ccw
  arc A18 (32.15, 12.8) -> (31.9, 12.55) centre (32.15, 12.55) ccw
  arc A19 (31.9, 12.25) -> (32.15, 12) centre (32.15, 12.25) ccw
  line L20 (27.75, 12) -> (30.25, 12)
  line L21 (30.5, 12.25) -> (30.5, 12.55)
  line L22 (30.25, 12.8) -> (27.75, 12.8)
  line L23 (27.5, 12.55) -> (27.5, 12.25)
  arc A20 (30.25, 12) -> (30.5, 12.25) centre (30.25, 12.25) ccw
  arc A21 (30.5, 12.55) -> (30.25, 12.8) centre (30.25, 12.55) ccw
  arc A22 (27.75, 12.8) -> (27.5, 12.55) centre (27.75, 12.55) ccw
  arc A23 (27.5, 12.25) -> (27.75, 12) centre (27.75, 12.25) ccw
  line L24 (23.35, 12) -> (25.85, 12)
  line L25 (26.1, 12.25) -> (26.1, 12.55)
  line L26 (25.85, 12.8) -> (23.35, 12.8)
  line L27 (23.1, 12.55) -> (23.1, 12.25)
  arc A24 (25.85, 12) -> (26.1, 12.25) centre (25.85, 12.25) ccw
  arc A25 (26.1, 12.55) -> (25.85, 12.8) centre (25.85, 12.55) ccw
  arc A26 (23.35, 12.8) -> (23.1, 12.55) centre (23.35, 12.55) ccw
  arc A27 (23.1, 12.25) -> (23.35, 12) centre (23.35, 12.25) ccw
  line L28 (18.95, 12) -> (21.45, 12)
  line L29 (21.7, 12.25) -> (21.7, 12.55)
  line L30 (21.45, 12.8) -> (18.95, 12.8)
  line L31 (18.7, 12.55) -> (18.7, 12.25)
  arc A28 (21.45, 12) -> (21.7, 12.25) centre (21.45, 12.25) ccw
  arc A29 (21.7, 12.55) -> (21.45, 12.8) centre (21.45, 12.55) ccw
  arc A30 (18.95, 12.8) -> (18.7, 12.55) centre (18.95, 12.55) ccw
  arc A31 (18.7, 12.25) -> (18.95, 12) centre (18.95, 12.25) ccw
  line L32 (14.55, 12) -> (17.05, 12)
  line L33 (17.3, 12.25) -> (17.3, 12.55)
  line L34 (17.05, 12.8) -> (14.55, 12.8)
  line L35 (14.3, 12.55) -> (14.3, 12.25)
  arc A32 (17.05, 12) -> (17.3, 12.25) centre (17.05, 12.25) ccw
  arc A33 (17.3, 12.55) -> (17.05, 12.8) centre (17.05, 12.55) ccw
  arc A34 (14.55, 12.8) -> (14.3, 12.55) centre (14.55, 12.55) ccw
  arc A35 (14.3, 12.25) -> (14.55, 12) centre (14.55, 12.25) ccw
  line L36 (49.75, 13.8) -> (52.25, 13.8)
  line L37 (52.5, 14.05) -> (52.5, 14.35)
  line L38 (52.25, 14.6) -> (49.75, 14.6)
  line L39 (49.5, 14.35) -> (49.5, 14.05)
  arc A36 (52.25, 13.8) -> (52.5, 14.05) centre (52.25, 14.05) ccw
  arc A37 (52.5, 14.35) -> (52.25, 14.6) centre (52.25, 14.35) ccw
  arc A38 (49.75, 14.6) -> (49.5, 14.35) centre (49.75, 14.35) ccw
  arc A39 (49.5, 14.05) -> (49.75, 13.8) centre (49.75, 14.05) ccw
  line L40 (45.35, 13.8) -> (47.85, 13.8)
  line L41 (48.1, 14.05) -> (48.1, 14.35)
  line L42 (47.85, 14.6) -> (45.35, 14.6)
  line L43 (45.1, 14.35) -> (45.1, 14.05)
  arc A40 (47.85, 13.8) -> (48.1, 14.05) centre (47.85, 14.05) ccw
  arc A41 (48.1, 14.35) -> (47.85, 14.6) centre (47.85, 14.35) ccw
  arc A42 (45.35, 14.6) -> (45.1, 14.35) centre (45.35, 14.35) ccw
  arc A43 (45.1, 14.05) -> (45.35, 13.8) centre (45.35, 14.05) ccw
  line L44 (40.95, 13.8) -> (43.45, 13.8)
  line L45 (43.7, 14.05) -> (43.7, 14.35)
  line L46 (43.45, 14.6) -> (40.95, 14.6)
  line L47 (40.7, 14.35) -> (40.7, 14.05)
  arc A44 (43.45, 13.8) -> (43.7, 14.05) centre (43.45, 14.05) ccw
  arc A45 (43.7, 14.35) -> (43.45, 14.6) centre (43.45, 14.35) ccw
  arc A46 (40.95, 14.6) -> (40.7, 14.35) centre (40.95, 14.35) ccw
  arc A47 (40.7, 14.05) -> (40.95, 13.8) centre (40.95, 14.05) ccw
  line L48 (36.55, 13.8) -> (39.05, 13.8)
  line L49 (39.3, 14.05) -> (39.3, 14.35)
  line L50 (39.05, 14.6) -> (36.55, 14.6)
  line L51 (36.3, 14.35) -> (36.3, 14.05)
  arc A48 (39.05, 13.8) -> (39.3, 14.05) centre (39.05, 14.05) ccw
  arc A49 (39.3, 14.35) -> (39.05, 14.6) centre (39.05, 14.35) ccw
  arc A50 (36.55, 14.6) -> (36.3, 14.35) centre (36.55, 14.35) ccw
  arc A51 (36.3, 14.05) -> (36.55, 13.8) centre (36.55, 14.05) ccw
  line L52 (32.15, 13.8) -> (34.65, 13.8)
  line L53 (34.9, 14.05) -> (34.9, 14.35)
  line L54 (34.65, 14.6) -> (32.15, 14.6)
  line L55 (31.9, 14.35) -> (31.9, 14.05)
  arc A52 (34.65, 13.8) -> (34.9, 14.05) centre (34.65, 14.05) ccw
  arc A53 (34.9, 14.35) -> (34.65, 14.6) centre (34.65, 14.35) ccw
  arc A54 (32.15, 14.6) -> (31.9, 14.35) centre (32.15, 14.35) ccw
  arc A55 (31.9, 14.05) -> (32.15, 13.8) centre (32.15, 14.05) ccw
  line L56 (27.75, 13.8) -> (30.25, 13.8)
  line L57 (30.5, 14.05) -> (30.5, 14.35)
  line L58 (30.25, 14.6) -> (27.75, 14.6)
  line L59 (27.5, 14.35) -> (27.5, 14.05)
  arc A56 (30.25, 13.8) -> (30.5, 14.05) centre (30.25, 14.05) ccw
  arc A57 (30.5, 14.35) -> (30.25, 14.6) centre (30.25, 14.35) ccw
  arc A58 (27.75, 14.6) -> (27.5, 14.35) centre (27.75, 14.35) ccw
  arc A59 (27.5, 14.05) -> (27.75, 13.8) centre (27.75, 14.05) ccw
  line L60 (23.35, 13.8) -> (25.85, 13.8)
  line L61 (26.1, 14.05) -> (26.1, 14.35)
  line L62 (25.85, 14.6) -> (23.35, 14.6)
  line L63 (23.1, 14.35) -> (23.1, 14.05)
  arc A60 (25.85, 13.8) -> (26.1, 14.05) centre (25.85, 14.05) ccw
  arc A61 (26.1, 14.35) -> (25.85, 14.6) centre (25.85, 14.35) ccw
  arc A62 (23.35, 14.6) -> (23.1, 14.35) centre (23.35, 14.35) ccw
  arc A63 (23.1, 14.05) -> (23.35, 13.8) centre (23.35, 14.05) ccw
  line L64 (18.95, 13.8) -> (21.45, 13.8)
  line L65 (21.7, 14.05) -> (21.7, 14.35)
  line L66 (21.45, 14.6) -> (18.95, 14.6)
  line L67 (18.7, 14.35) -> (18.7, 14.05)
  arc A64 (21.45, 13.8) -> (21.7, 14.05) centre (21.45, 14.05) ccw
  arc A65 (21.7, 14.35) -> (21.45, 14.6) centre (21.45, 14.35) ccw
  arc A66 (18.95, 14.6) -> (18.7, 14.35) centre (18.95, 14.35) ccw
  arc A67 (18.7, 14.05) -> (18.95, 13.8) centre (18.95, 14.05) ccw
  line L68 (14.55, 13.8) -> (17.05, 13.8)
  line L69 (17.3, 14.05) -> (17.3, 14.35)
  line L70 (17.05, 14.6) -> (14.55, 14.6)
  line L71 (14.3, 14.35) -> (14.3, 14.05)
  arc A68 (17.05, 13.8) -> (17.3, 14.05) centre (17.05, 14.05) ccw
  arc A69 (17.3, 14.35) -> (17.05, 14.6) centre (17.05, 14.35) ccw
  arc A70 (14.55, 14.6) -> (14.3, 14.35) centre (14.55, 14.35) ccw
  arc A71 (14.3, 14.05) -> (14.55, 13.8) centre (14.55, 14.05) ccw
  line L72 (49.75, 15.6) -> (52.25, 15.6)
  line L73 (52.5, 15.85) -> (52.5, 16.15)
  line L74 (52.25, 16.4) -> (49.75, 16.4)
  line L75 (49.5, 16.15) -> (49.5, 15.85)
  arc A72 (52.25, 15.6) -> (52.5, 15.85) centre (52.25, 15.85) ccw
  arc A73 (52.5, 16.15) -> (52.25, 16.4) centre (52.25, 16.15) ccw
  arc A74 (49.75, 16.4) -> (49.5, 16.15) centre (49.75, 16.15) ccw
  arc A75 (49.5, 15.85) -> (49.75, 15.6) centre (49.75, 15.85) ccw
  line L76 (45.35, 15.6) -> (47.85, 15.6)
  line L77 (48.1, 15.85) -> (48.1, 16.15)
  line L78 (47.85, 16.4) -> (45.35, 16.4)
  line L79 (45.1, 16.15) -> (45.1, 15.85)
  arc A76 (47.85, 15.6) -> (48.1, 15.85) centre (47.85, 15.85) ccw
  arc A77 (48.1, 16.15) -> (47.85, 16.4) centre (47.85, 16.15) ccw
  arc A78 (45.35, 16.4) -> (45.1, 16.15) centre (45.35, 16.15) ccw
  arc A79 (45.1, 15.85) -> (45.35, 15.6) centre (45.35, 15.85) ccw
  line L80 (40.95, 15.6) -> (43.45, 15.6)
  line L81 (43.7, 15.85) -> (43.7, 16.15)
  line L82 (43.45, 16.4) -> (40.95, 16.4)
  line L83 (40.7, 16.15) -> (40.7, 15.85)
  arc A80 (43.45, 15.6) -> (43.7, 15.85) centre (43.45, 15.85) ccw
  arc A81 (43.7, 16.15) -> (43.45, 16.4) centre (43.45, 16.15) ccw
  arc A82 (40.95, 16.4) -> (40.7, 16.15) centre (40.95, 16.15) ccw
  arc A83 (40.7, 15.85) -> (40.95, 15.6) centre (40.95, 15.85) ccw
  line L84 (36.55, 15.6) -> (39.05, 15.6)
  line L85 (39.3, 15.85) -> (39.3, 16.15)
  line L86 (39.05, 16.4) -> (36.55, 16.4)
  line L87 (36.3, 16.15) -> (36.3, 15.85)
  arc A84 (39.05, 15.6) -> (39.3, 15.85) centre (39.05, 15.85) ccw
  arc A85 (39.3, 16.15) -> (39.05, 16.4) centre (39.05, 16.15) ccw
  arc A86 (36.55, 16.4) -> (36.3, 16.15) centre (36.55, 16.15) ccw
  arc A87 (36.3, 15.85) -> (36.55, 15.6) centre (36.55, 15.85) ccw
  line L88 (32.15, 15.6) -> (34.65, 15.6)
  line L89 (34.9, 15.85) -> (34.9, 16.15)
  line L90 (34.65, 16.4) -> (32.15, 16.4)
  line L91 (31.9, 16.15) -> (31.9, 15.85)
  arc A88 (34.65, 15.6) -> (34.9, 15.85) centre (34.65, 15.85) ccw
  arc A89 (34.9, 16.15) -> (34.65, 16.4) centre (34.65, 16.15) ccw
  arc A90 (32.15, 16.4) -> (31.9, 16.15) centre (32.15, 16.15) ccw
  arc A91 (31.9, 15.85) -> (32.15, 15.6) centre (32.15, 15.85) ccw
  line L92 (27.75, 15.6) -> (30.25, 15.6)
  line L93 (30.5, 15.85) -> (30.5, 16.15)
  line L94 (30.25, 16.4) -> (27.75, 16.4)
  line L95 (27.5, 16.15) -> (27.5, 15.85)
  arc A92 (30.25, 15.6) -> (30.5, 15.85) centre (30.25, 15.85) ccw
  arc A93 (30.5, 16.15) -> (30.25, 16.4) centre (30.25, 16.15) ccw
  arc A94 (27.75, 16.4) -> (27.5, 16.15) centre (27.75, 16.15) ccw
  arc A95 (27.5, 15.85) -> (27.75, 15.6) centre (27.75, 15.85) ccw
  line L96 (23.35, 15.6) -> (25.85, 15.6)
  line L97 (26.1, 15.85) -> (26.1, 16.15)
  line L98 (25.85, 16.4) -> (23.35, 16.4)
  line L99 (23.1, 16.15) -> (23.1, 15.85)
  arc A96 (25.85, 15.6) -> (26.1, 15.85) centre (25.85, 15.85) ccw
  arc A97 (26.1, 16.15) -> (25.85, 16.4) centre (25.85, 16.15) ccw
  arc A98 (23.35, 16.4) -> (23.1, 16.15) centre (23.35, 16.15) ccw
  arc A99 (23.1, 15.85) -> (23.35, 15.6) centre (23.35, 15.85) ccw
  line L100 (18.95, 15.6) -> (21.45, 15.6)
  line L101 (21.7, 15.85) -> (21.7, 16.15)
  line L102 (21.45, 16.4) -> (18.95, 16.4)
  line L103 (18.7, 16.15) -> (18.7, 15.85)
  arc A100 (21.45, 15.6) -> (21.7, 15.85) centre (21.45, 15.85) ccw
  arc A101 (21.7, 16.15) -> (21.45, 16.4) centre (21.45, 16.15) ccw
  arc A102 (18.95, 16.4) -> (18.7, 16.15) centre (18.95, 16.15) ccw
  arc A103 (18.7, 15.85) -> (18.95, 15.6) centre (18.95, 15.85) ccw
  line L104 (14.55, 15.6) -> (17.05, 15.6)
  line L105 (17.3, 15.85) -> (17.3, 16.15)
  line L106 (17.05, 16.4) -> (14.55, 16.4)
  line L107 (14.3, 16.15) -> (14.3, 15.85)
  arc A104 (17.05, 15.6) -> (17.3, 15.85) centre (17.05, 15.85) ccw
  arc A105 (17.3, 16.15) -> (17.05, 16.4) centre (17.05, 16.15) ccw
  arc A106 (14.55, 16.4) -> (14.3, 16.15) centre (14.55, 16.15) ccw
  arc A107 (14.3, 15.85) -> (14.55, 15.6) centre (14.55, 15.85) ccw
  line L108 (49.75, 17.4) -> (52.25, 17.4)
  line L109 (52.5, 17.65) -> (52.5, 17.95)
  line L110 (52.25, 18.2) -> (49.75, 18.2)
  line L111 (49.5, 17.95) -> (49.5, 17.65)
  arc A108 (52.25, 17.4) -> (52.5, 17.65) centre (52.25, 17.65) ccw
  arc A109 (52.5, 17.95) -> (52.25, 18.2) centre (52.25, 17.95) ccw
  arc A110 (49.75, 18.2) -> (49.5, 17.95) centre (49.75, 17.95) ccw
  arc A111 (49.5, 17.65) -> (49.75, 17.4) centre (49.75, 17.65) ccw
  line L112 (45.35, 17.4) -> (47.85, 17.4)
  line L113 (48.1, 17.65) -> (48.1, 17.95)
  line L114 (47.85, 18.2) -> (45.35, 18.2)
  line L115 (45.1, 17.95) -> (45.1, 17.65)
  arc A112 (47.85, 17.4) -> (48.1, 17.65) centre (47.85, 17.65) ccw
  arc A113 (48.1, 17.95) -> (47.85, 18.2) centre (47.85, 17.95) ccw
  arc A114 (45.35, 18.2) -> (45.1, 17.95) centre (45.35, 17.95) ccw
  arc A115 (45.1, 17.65) -> (45.35, 17.4) centre (45.35, 17.65) ccw
  line L116 (40.95, 17.4) -> (43.45, 17.4)
  line L117 (43.7, 17.65) -> (43.7, 17.95)
  line L118 (43.45, 18.2) -> (40.95, 18.2)
  line L119 (40.7, 17.95) -> (40.7, 17.65)
  arc A116 (43.45, 17.4) -> (43.7, 17.65) centre (43.45, 17.65) ccw
  arc A117 (43.7, 17.95) -> (43.45, 18.2) centre (43.45, 17.95) ccw
  arc A118 (40.95, 18.2) -> (40.7, 17.95) centre (40.95, 17.95) ccw
  arc A119 (40.7, 17.65) -> (40.95, 17.4) centre (40.95, 17.65) ccw
  line L120 (36.55, 17.4) -> (39.05, 17.4)
  line L121 (39.3, 17.65) -> (39.3, 17.95)
  line L122 (39.05, 18.2) -> (36.55, 18.2)
  line L123 (36.3, 17.95) -> (36.3, 17.65)
  arc A120 (39.05, 17.4) -> (39.3, 17.65) centre (39.05, 17.65) ccw
  arc A121 (39.3, 17.95) -> (39.05, 18.2) centre (39.05, 17.95) ccw
  arc A122 (36.55, 18.2) -> (36.3, 17.95) centre (36.55, 17.95) ccw
  arc A123 (36.3, 17.65) -> (36.55, 17.4) centre (36.55, 17.65) ccw
  line L124 (32.15, 17.4) -> (34.65, 17.4)
  line L125 (34.9, 17.65) -> (34.9, 17.95)
  line L126 (34.65, 18.2) -> (32.15, 18.2)
  line L127 (31.9, 17.95) -> (31.9, 17.65)
  arc A124 (34.65, 17.4) -> (34.9, 17.65) centre (34.65, 17.65) ccw
  arc A125 (34.9, 17.95) -> (34.65, 18.2) centre (34.65, 17.95) ccw
  arc A126 (32.15, 18.2) -> (31.9, 17.95) centre (32.15, 17.95) ccw
  arc A127 (31.9, 17.65) -> (32.15, 17.4) centre (32.15, 17.65) ccw
  line L128 (27.75, 17.4) -> (30.25, 17.4)
  line L129 (30.5, 17.65) -> (30.5, 17.95)
  line L130 (30.25, 18.2) -> (27.75, 18.2)
  line L131 (27.5, 17.95) -> (27.5, 17.65)
  arc A128 (30.25, 17.4) -> (30.5, 17.65) centre (30.25, 17.65) ccw
  arc A129 (30.5, 17.95) -> (30.25, 18.2) centre (30.25, 17.95) ccw
  arc A130 (27.75, 18.2) -> (27.5, 17.95) centre (27.75, 17.95) ccw
  arc A131 (27.5, 17.65) -> (27.75, 17.4) centre (27.75, 17.65) ccw
  line L132 (23.35, 17.4) -> (25.85, 17.4)
  line L133 (26.1, 17.65) -> (26.1, 17.95)
  line L134 (25.85, 18.2) -> (23.35, 18.2)
  line L135 (23.1, 17.95) -> (23.1, 17.65)
  arc A132 (25.85, 17.4) -> (26.1, 17.65) centre (25.85, 17.65) ccw
  arc A133 (26.1, 17.95) -> (25.85, 18.2) centre (25.85, 17.95) ccw
  arc A134 (23.35, 18.2) -> (23.1, 17.95) centre (23.35, 17.95) ccw
  arc A135 (23.1, 17.65) -> (23.35, 17.4) centre (23.35, 17.65) ccw
  line L136 (18.95, 17.4) -> (21.45, 17.4)
  line L137 (21.7, 17.65) -> (21.7, 17.95)
  line L138 (21.45, 18.2) -> (18.95, 18.2)
  line L139 (18.7, 17.95) -> (18.7, 17.65)
  arc A136 (21.45, 17.4) -> (21.7, 17.65) centre (21.45, 17.65) ccw
  arc A137 (21.7, 17.95) -> (21.45, 18.2) centre (21.45, 17.95) ccw
  arc A138 (18.95, 18.2) -> (18.7, 17.95) centre (18.95, 17.95) ccw
  arc A139 (18.7, 17.65) -> (18.95, 17.4) centre (18.95, 17.65) ccw
  line L140 (14.55, 17.4) -> (17.05, 17.4)
  line L141 (17.3, 17.65) -> (17.3, 17.95)
  line L142 (17.05, 18.2) -> (14.55, 18.2)
  line L143 (14.3, 17.95) -> (14.3, 17.65)
  arc A140 (17.05, 17.4) -> (17.3, 17.65) centre (17.05, 17.65) ccw
  arc A141 (17.3, 17.95) -> (17.05, 18.2) centre (17.05, 17.95) ccw
  arc A142 (14.55, 18.2) -> (14.3, 17.95) centre (14.55, 17.95) ccw
  arc A143 (14.3, 17.65) -> (14.55, 17.4) centre (14.55, 17.65) ccw
  constraint tangent L0 A0
  constraint tangent L1 A0
  constraint tangent L1 A1
  constraint tangent L2 A1
  constraint tangent L2 A2
  constraint tangent L3 A2
  constraint tangent L3 A3
  constraint tangent L0 A3
  constraint tangent L4 A4
  constraint tangent L5 A4
  constraint tangent L5 A5
  constraint tangent L6 A5
  constraint tangent L6 A6
  constraint tangent L7 A6
  constraint tangent L7 A7
  constraint tangent L4 A7
  constraint tangent L8 A8
  constraint tangent L9 A8
  constraint tangent L9 A9
  constraint tangent L10 A9
  constraint tangent L10 A10
  constraint tangent L11 A10
  constraint tangent L11 A11
  constraint tangent L8 A11
  constraint tangent L12 A12
  constraint tangent L13 A12
  constraint tangent L13 A13
  constraint tangent L14 A13
  constraint tangent L14 A14
  constraint tangent L15 A14
  constraint tangent L15 A15
  constraint tangent L12 A15
  constraint tangent L16 A16
  constraint tangent L17 A16
  constraint tangent L17 A17
  constraint tangent L18 A17
  constraint tangent L18 A18
  constraint tangent L19 A18
  constraint tangent L19 A19
  constraint tangent L16 A19
  constraint tangent L20 A20
  constraint tangent L21 A20
  constraint tangent L21 A21
  constraint tangent L22 A21
  constraint tangent L22 A22
  constraint tangent L23 A22
  constraint tangent L23 A23
  constraint tangent L20 A23
  constraint tangent L24 A24
  constraint tangent L25 A24
  constraint tangent L25 A25
  constraint tangent L26 A25
  constraint tangent L26 A26
  constraint tangent L27 A26
  constraint tangent L27 A27
  constraint tangent L24 A27
  constraint tangent L28 A28
  constraint tangent L29 A28
  constraint tangent L29 A29
  constraint tangent L30 A29
  constraint tangent L30 A30
  constraint tangent L31 A30
  constraint tangent L31 A31
  constraint tangent L28 A31
  constraint tangent L32 A32
  constraint tangent L33 A32
  constraint tangent L33 A33
  constraint tangent L34 A33
  constraint tangent L34 A34
  constraint tangent L35 A34
  constraint tangent L35 A35
  constraint tangent L32 A35
  constraint tangent L36 A36
  constraint tangent L37 A36
  constraint tangent L37 A37
  constraint tangent L38 A37
  constraint tangent L38 A38
  constraint tangent L39 A38
  constraint tangent L39 A39
  constraint tangent L36 A39
  constraint tangent L40 A40
  constraint tangent L41 A40
  constraint tangent L41 A41
  constraint tangent L42 A41
  constraint tangent L42 A42
  constraint tangent L43 A42
  constraint tangent L43 A43
  constraint tangent L40 A43
  constraint tangent L44 A44
  constraint tangent L45 A44
  constraint tangent L45 A45
  constraint tangent L46 A45
  constraint tangent L46 A46
  constraint tangent L47 A46
  constraint tangent L47 A47
  constraint tangent L44 A47
  constraint tangent L48 A48
  constraint tangent L49 A48
  constraint tangent L49 A49
  constraint tangent L50 A49
  constraint tangent L50 A50
  constraint tangent L51 A50
  constraint tangent L51 A51
  constraint tangent L48 A51
  constraint tangent L52 A52
  constraint tangent L53 A52
  constraint tangent L53 A53
  constraint tangent L54 A53
  constraint tangent L54 A54
  constraint tangent L55 A54
  constraint tangent L55 A55
  constraint tangent L52 A55
  constraint tangent L56 A56
  constraint tangent L57 A56
  constraint tangent L57 A57
  constraint tangent L58 A57
  constraint tangent L58 A58
  constraint tangent L59 A58
  constraint tangent L59 A59
  constraint tangent L56 A59
  constraint tangent L60 A60
  constraint tangent L61 A60
  constraint tangent L61 A61
  constraint tangent L62 A61
  constraint tangent L62 A62
  constraint tangent L63 A62
  constraint tangent L63 A63
  constraint tangent L60 A63
  constraint tangent L64 A64
  constraint tangent L65 A64
  constraint tangent L65 A65
  constraint tangent L66 A65
  constraint tangent L66 A66
  constraint tangent L67 A66
  constraint tangent L67 A67
  constraint tangent L64 A67
  constraint tangent L68 A68
  constraint tangent L69 A68
  constraint tangent L69 A69
  constraint tangent L70 A69
  constraint tangent L70 A70
  constraint tangent L71 A70
  constraint tangent L71 A71
  constraint tangent L68 A71
  constraint tangent L72 A72
  constraint tangent L73 A72
  constraint tangent L73 A73
  constraint tangent L74 A73
  constraint tangent L74 A74